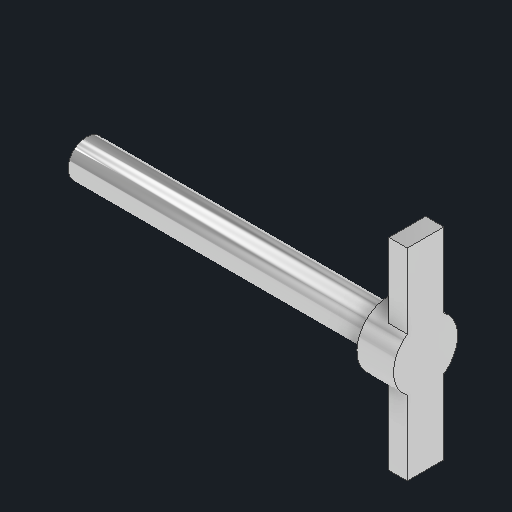
# Autodesk Inventor part: latitude_tbolt
Saved by Autodesk Inventor 2027.1 (Build 311270010, 270A)
## iProperties
Created: 2026-11-04
Part Number: latitude_tbolt
Material: Generic
Description: Latitude adjustment T-bolt
Document SubType Name: Modeling
Designer: Claude (from photos)
Density: 1 g/cm^3
Appearance: Chrome - Polished
Author: alexg
Autodesk Inventor part; units mm, degrees
ref_plane "XZ Plane" through (0, 0, 0) normal (0, 1, 0) x (-1, 0, 0)
sketch "Threaded rod M8 sketch" plane through (0, 0, 0) normal (1, 0, 0) x (0, 1, 0)
  circle A0 centre (0, 0) radius 4
  constraints: 1 centre point
extrude "Threaded rod M8" add sketch "Threaded rod M8 sketch" along normal blind 74
ref_plane "Work Plane1" through (66, 0, 0) normal (1, 0, 0) x (0, 1, 0)
sketch "Handle boss sketch" plane through (66, 0, 0) normal (1, 0, 0) x (0, 1, 0)
  circle A0 centre (0, 0) radius 7
  constraints: 1 centre point
extrude "Handle boss" add sketch "Handle boss sketch" along normal blind 8
ref_plane "Work Plane2" through (70, 0, 0) normal (1, 0, 0) x (0, 1, 0)
sketch "T handle sketch" plane through (70, 0, 0) normal (1, 0, 0) x (0, 1, 0)
  line L0 (-22, -4) -> (22, -4)
  line L1 (22, -4) -> (22, 4)
  line L2 (22, 4) -> (-22, 4)
  line L3 (-22, 4) -> (-22, -4)
  constraints: 8 end point, 2 parallel, 1 horizontal, 1 perpendicular
extrude "T handle" add sketch "T handle sketch" along normal blind 4
body "Solid1"
